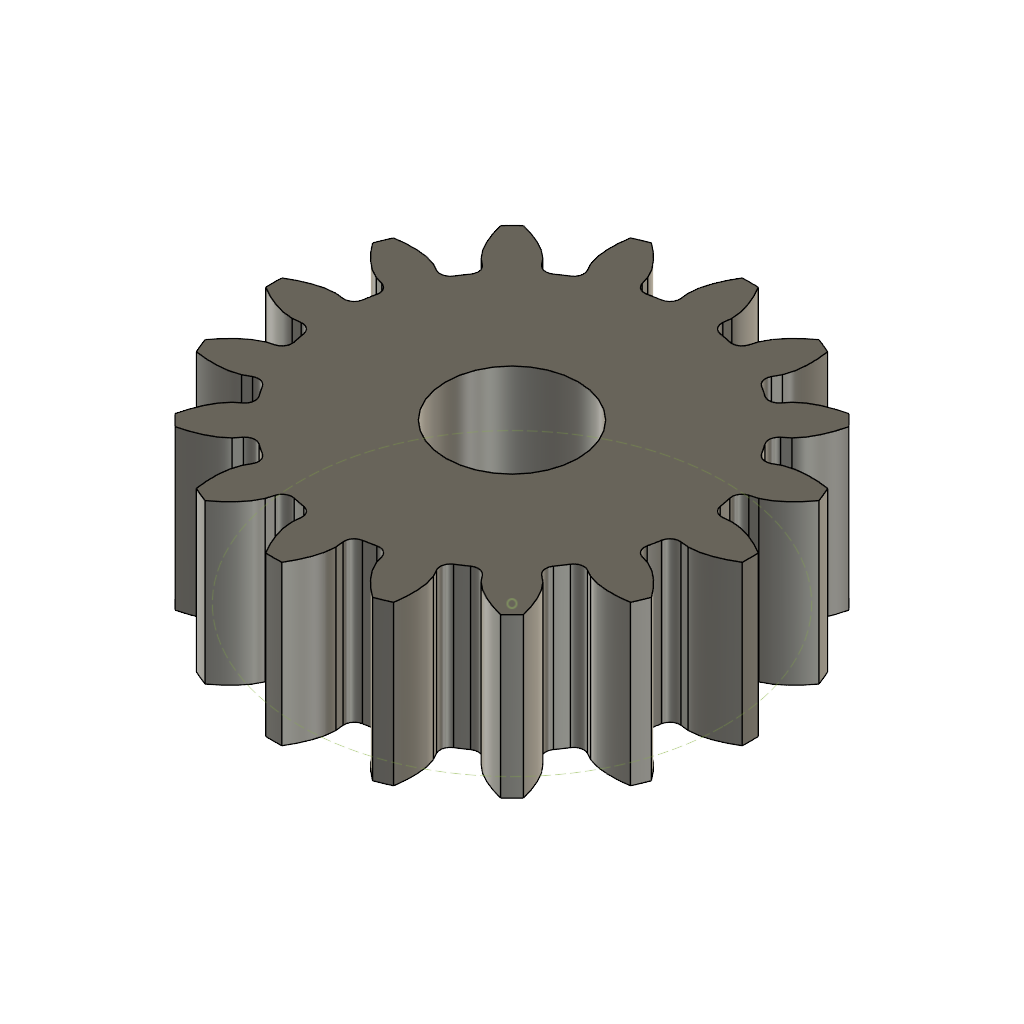
RA4_Arm_Mustafa_Ali_Mohsin_Albusultan (Autodesk Fusion 360 archive; units mm, degrees)
design "Pinion"
description: Spur Gear; Module: 1.0; Num Teeth: 16; Pressure Angle: 20.0; Backlash: 0.10 mm
part number: 2026-10-20-01-23-52-985
Autodesk Fusion 360 part; units mm, degrees
sketch "Base Circle" plane through (0, 0, 0) normal (0, 0, 1) x (1, 0, 0)
  circle A0 centre (0, 0) radius 6.843
  circle A1 centre (0, 0) radius 2.5
extrude "Extrude1" add sketch "Base Circle" along normal blind 6
sketch "Gear Tooth" plane through (0, 0, 0) normal (0, 0, 1) x (1, 0, 0)
  spline S0 degree 5 poles (7.4721, -0.8249) (7.4765, -0.8254) (7.4851, -0.8262) (7.4981, -0.8271) (7.5154, -0.8276) (7.5371, -0.8272) (7.5589, -0.8261) (7.5806, -0.8246) (7.6025, -0.8228) (7.6243, -0.8209) (7.6462, -0.8188) (7.668, -0.8165) (7.6899, -0.814) (7.7118, -0.811) (7.7337, -0.8078) (7.7557, -0.8042) (7.7776, -0.8003) (7.7995, -0.7963) (7.8215, -0.792) (7.8434, -0.7875) (7.8654, -0.7828) (7.8873, -0.778) (7.9093, -0.7729) (7.9312, -0.7676) (7.9532, -0.7621) (7.9752, -0.7564) (7.9971, -0.7505) (8.0191, -0.7444) (8.041, -0.7381) (8.063, -0.7316) (8.0849, -0.725) (8.1069, -0.7182) (8.1288, -0.7112) (8.1507, -0.704) (8.1727, -0.6967) (8.1946, -0.6892) (8.2165, -0.6815) (8.2384, -0.6737) (8.2603, -0.6657) (8.2821, -0.6575) (8.304, -0.6492) (8.3258, -0.6407) (8.3477, -0.632) (8.3695, -0.6232) (8.3913, -0.6143) (8.4131, -0.6052) (8.4349, -0.5959) (8.4567, -0.5865) (8.4785, -0.5769) (8.5002, -0.5672) (8.5219, -0.5574) (8.5436, -0.5473) (8.5653, -0.5372) (8.587, -0.5269) (8.6087, -0.5164) (8.6303, -0.5058) (8.6519, -0.4951) (8.6735, -0.4842) (8.6951, -0.4732) (8.7167, -0.4621) (8.7382, -0.4508) (8.7597, -0.4394) (8.7812, -0.4278) (8.8027, -0.4161) (8.8241, -0.4042) (8.8456, -0.3923) (8.867, -0.3802) (8.8883, -0.3679) (8.9097, -0.3555) (8.931, -0.343) (8.9523, -0.3304) (8.9693, -0.3202) (8.9821, -0.3124) (8.9906, -0.3073) (8.9948, -0.3047) knots 0 0 0 0 0 0 0.01428571 0.02857143 0.04285714 0.05714286 0.07142857 0.08571429 0.1 0.11428571 0.12857143 0.14285714 0.15714286 0.17142857 0.18571429 0.2 0.21428571 0.22857143 0.24285714 0.25714286 0.27142857 0.28571429 0.3 0.31428571 0.32857143 0.34285714 0.35714286 0.37142857 0.38571429 0.4 0.41428571 0.42857143 0.44285714 0.45714286 0.47142857 0.48571429 0.5 0.51428571 0.52857143 0.54285714 0.55714286 0.57142857 0.58571429 0.6 0.61428571 0.62857143 0.64285714 0.65714286 0.67142857 0.68571429 0.7 0.71428571 0.72857143 0.74285714 0.75714286 0.77142857 0.78571429 0.8 0.81428571 0.82857143 0.84285714 0.85714286 0.87142857 0.88571429 0.9 0.91428571 0.92857143 0.94285714 0.95714286 0.97142857 0.98571429 1 1 1 1 1 1
  spline S1 degree 5 poles (7.4721, 0.8249) (7.4765, 0.8254) (7.4851, 0.8262) (7.4981, 0.8271) (7.5154, 0.8276) (7.5371, 0.8272) (7.5589, 0.8261) (7.5806, 0.8246) (7.6025, 0.8228) (7.6243, 0.8209) (7.6462, 0.8188) (7.668, 0.8165) (7.6899, 0.814) (7.7118, 0.811) (7.7337, 0.8078) (7.7557, 0.8042) (7.7776, 0.8003) (7.7995, 0.7963) (7.8215, 0.792) (7.8434, 0.7875) (7.8654, 0.7828) (7.8873, 0.778) (7.9093, 0.7729) (7.9312, 0.7676) (7.9532, 0.7621) (7.9752, 0.7564) (7.9971, 0.7505) (8.0191, 0.7444) (8.041, 0.7381) (8.063, 0.7316) (8.0849, 0.725) (8.1069, 0.7182) (8.1288, 0.7112) (8.1507, 0.704) (8.1727, 0.6967) (8.1946, 0.6892) (8.2165, 0.6815) (8.2384, 0.6737) (8.2603, 0.6657) (8.2821, 0.6575) (8.304, 0.6492) (8.3258, 0.6407) (8.3477, 0.632) (8.3695, 0.6232) (8.3913, 0.6143) (8.4131, 0.6052) (8.4349, 0.5959) (8.4567, 0.5865) (8.4785, 0.5769) (8.5002, 0.5672) (8.5219, 0.5574) (8.5436, 0.5473) (8.5653, 0.5372) (8.587, 0.5269) (8.6087, 0.5164) (8.6303, 0.5058) (8.6519, 0.4951) (8.6735, 0.4842) (8.6951, 0.4732) (8.7167, 0.4621) (8.7382, 0.4508) (8.7597, 0.4394) (8.7812, 0.4278) (8.8027, 0.4161) (8.8241, 0.4042) (8.8456, 0.3923) (8.867, 0.3802) (8.8883, 0.3679) (8.9097, 0.3555) (8.931, 0.343) (8.9523, 0.3304) (8.9693, 0.3202) (8.9821, 0.3124) (8.9906, 0.3073) (8.9948, 0.3047) knots 0 0 0 0 0 0 0.01428571 0.02857143 0.04285714 0.05714286 0.07142857 0.08571429 0.1 0.11428571 0.12857143 0.14285714 0.15714286 0.17142857 0.18571429 0.2 0.21428571 0.22857143 0.24285714 0.25714286 0.27142857 0.28571429 0.3 0.31428571 0.32857143 0.34285714 0.35714286 0.37142857 0.38571429 0.4 0.41428571 0.42857143 0.44285714 0.45714286 0.47142857 0.48571429 0.5 0.51428571 0.52857143 0.54285714 0.55714286 0.57142857 0.58571429 0.6 0.61428571 0.62857143 0.64285714 0.65714286 0.67142857 0.68571429 0.7 0.71428571 0.72857143 0.74285714 0.75714286 0.77142857 0.78571429 0.8 0.81428571 0.82857143 0.84285714 0.85714286 0.87142857 0.88571429 0.9 0.91428571 0.92857143 0.94285714 0.95714286 0.97142857 0.98571429 1 1 1 1 1 1
  arc A0 (8.9948, -0.3047) -> (8.9948, 0.3047) centre (0, 0) ccw
  line L0 (6.7917, -0.7498) -> (7.4721, -0.8249)
  line L1 (6.7917, 0.7498) -> (7.4721, 0.8249)
  line L2 (6.7917, -0.7498) -> (6.7917, 0.7498)
  point P0 (7.5787, -0.8247)
  point P1 (7.6863, -0.8143)
  point P2 (7.7946, -0.7971)
  point P3 (7.9033, -0.7742)
  point P4 (8.0123, -0.7462)
  point P5 (8.1216, -0.7135)
  point P6 (8.231, -0.6763)
  point P7 (8.3405, -0.6349)
  point P8 (8.45, -0.5894)
  point P9 (8.5594, -0.5399)
  point P10 (8.6687, -0.4867)
  point P11 (8.7777, -0.4296)
  point P12 (8.8865, -0.369)
  point P13 (7.5787, 0.8247)
  point P14 (7.6863, 0.8143)
  point P15 (7.7946, 0.7971)
  point P16 (7.9033, 0.7742)
  point P17 (8.0123, 0.7462)
  point P18 (8.1216, 0.7135)
  point P19 (8.231, 0.6763)
  point P20 (8.3405, 0.6349)
  point P21 (8.45, 0.5894)
  point P22 (8.5594, 0.5399)
  point P23 (8.6687, 0.4867)
  point P24 (8.7777, 0.4296)
  point P25 (8.8865, 0.369)
extrude "Extrude2" add sketch "Gear Tooth" along normal blind 6
fillet "Fillet1" radius 0.38 2 edges at (6.8017, -0.7509, 3) (6.8017, 0.7509, 3)
pattern_circular "C-Pattern1" count 16 over 360 about axis through (0, 0, 0) along (0, 0, 1) of "Extrude2", "Fillet1"
sketch "Diametrial Pitch Circle" plane through (0, 0, 0) normal (0, 0, 1) x (1, 0, 0)
  circle A0 centre (0, 0) radius 8 construction
